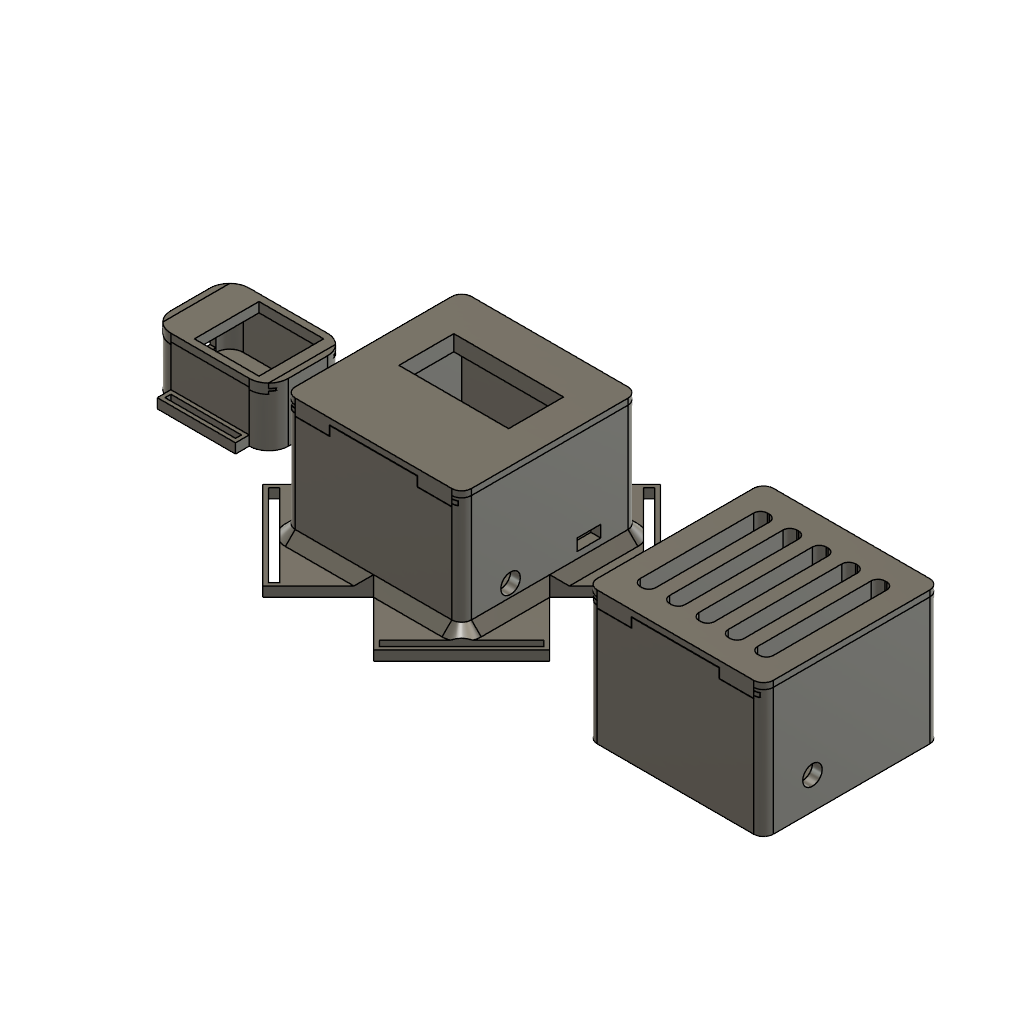
Vishwakarma (Autodesk Fusion 360 design; units mm, degrees)
Autodesk Fusion 360 part; units mm, degrees
sketch "Sketch1" plane through (0, 0, 0) normal (0, 1, 0) x (1, 0, 0) in component "Wrist unit"
  line L0 (20, 20) -> (-20, 20)
  line L1 (-30, 10) -> (-30, -10)
  line L2 (-20, -20) -> (20, -20)
  line L3 (30, -10) -> (30, 10)
  line L4 (30, 20) -> (-30, -20) construction
  line L5 (-30, 20) -> (30, -20) construction
  arc A0 (-20, 20) -> (-30, 10) centre (-20, 10) ccw
  arc A1 (30, 10) -> (20, 20) centre (20, 10) ccw
  arc A2 (20, -20) -> (30, -10) centre (20, -10) ccw
  arc A3 (-30, -10) -> (-20, -20) centre (-20, -10) ccw
  line L6 (-30, 0) -> (30, 0) construction
  line L7 (0, 0) -> (-30, 0) construction
  line L8 (0, 20) -> (0, -20) construction
  line L9 (5, -5) -> (-5, -5)
  line L10 (-5, -5) -> (-5, 5)
  line L11 (-5, 5) -> (5, 5)
  line L12 (5, 5) -> (5, -5)
  line L13 (5, -5) -> (-5, 5) construction
  line L14 (-5, -5) -> (5, 5) construction
  line L15 (-20, 20) -> (20, 20)
  line L16 (20, 20) -> (20, 27)
  line L17 (20, 27) -> (-20, 27)
  line L18 (-20, 27) -> (-20, 20)
  line L19 (-20, -20) -> (20, -20)
  line L20 (20, -20) -> (20, -27)
  line L21 (20, -27) -> (-20, -27)
  line L22 (-20, -27) -> (-20, -20)
  line L23 (-18, 22) -> (18, 22)
  line L24 (18, 22) -> (18, 25)
  line L25 (18, 25) -> (-18, 25)
  line L26 (-18, 25) -> (-18, 22)
  line L27 (-18, -22) -> (18, -22)
  line L28 (18, -22) -> (18, -25)
  line L29 (18, -25) -> (-18, -25)
  line L30 (-18, -25) -> (-18, -22)
  line L31 (30, 0) -> (5, 0) construction
  line L32 (-11.5, -16.5) -> (21.5, -16.5)
  line L33 (21.5, -16.5) -> (21.5, 16.5)
  line L34 (21.5, 16.5) -> (-11.5, 16.5)
  line L35 (-11.5, 16.5) -> (-11.5, -16.5)
  line L36 (-11.5, -16.5) -> (21.5, 16.5) construction
  line L37 (21.5, -16.5) -> (-11.5, 16.5) construction
  point P0 (5, 0)
  dimension "d219_1" = 60
  dimension "d220_1" = 40
  dimension "d221_1" = 10
  dimension "d222_1" = 10
  dimension "d113" = 10
  dimension "d114" = 10
  dimension "d115" = 40
  dimension "d116" = 7
  dimension "d117" = 40
  dimension "d118" = 7
  dimension "d119" = -2
  dimension "d120" = 2
  dimension "d124" = 25
  dimension "d125" = 33
  dimension "d126" = 33
  constraint horizontal L0
  constraint perpendicular L0 L1
  constraint parallel L0 L2
  constraint parallel L1 L3
  constraint coincident L4 L7.start
  constraint coincident L5 L7.start
  constraint coincident L7.start origin
  constraint coincident L5.start L1
  constraint coincident L5.start L0
  constraint tangent L1 A0
  constraint tangent L0 A0
  constraint coincident L4.start L3
  constraint coincident L4.start L0
  constraint tangent L3 A1
  constraint tangent L0 A1
  constraint coincident L5.end L3
  constraint coincident L5.end L2
  constraint tangent L3 A2
  constraint tangent L2 A2
  constraint equal A1 A2
  constraint coincident L4.end L1
  constraint coincident L4.end L2
  constraint tangent L1 A3
  constraint tangent L2 A3
  constraint equal A1 A3
  constraint midpoint L1 L6.start
  constraint midpoint L3 L6.end
  constraint midpoint L0 L8.start
  constraint midpoint L2 L8.end
  constraint horizontal L9
  constraint perpendicular L9 L10
  constraint parallel L9 L11
  constraint parallel L10 L12
  constraint coincident L13 L7.start
  constraint coincident L14 L7.start
  constraint horizontal L15
  constraint vertical L16
  constraint horizontal L17
  constraint vertical L18
  constraint horizontal L19
  constraint vertical L20
  constraint horizontal L21
  constraint vertical L22
  constraint parallel L6 L31
  constraint horizontal L32
  constraint perpendicular L32 L33
  constraint parallel L32 L34
  constraint parallel L33 L35
  constraint coincident L36 P0
  constraint coincident L37 P0
  constraint coincident P0 L31.end
  measures "d219_1" distance of L4.end L5.end
  measures "d220_1" distance of L5.start L4.end
  measures "d221_1" radius of A0
  measures "d222_1" radius of A1
  measures "d113" distance of L10.end L11.end
  measures "d114" distance of L9.end L10.end
  measures "d115" distance of L0.end L0.start
  measures "d116" distance of L0.end L17.end
  measures "d117" distance of L2.start L2.end
  measures "d118" distance of L2.start L21.end
  measures "d124" distance of L6.end P0
  measures "d125" distance of L33.end L34.end
  measures "d126" distance of L32.end L33.end
extrude "Extrude1" add sketch "Sketch1" against normal blind 25 contours L0 L1 L2 L3 A0 A1 A2 A3 L15 L19 | L9 L10 L11 L12 | L32 L33 L34 L35 makes body 1 in component "Wrist unit"
shell "Shell1" thickness 3 removed faces 1 at (-6.6667, 0, 6.6667) on bodies 1 in component "Wrist unit"
extrude "Extrude2" cut sketch "Sketch1" against normal blind 25 contours L9 L10 L11 L12 bodies 1 in component "Wrist unit"
extrude "Extrude3" add sketch "Sketch1" along normal blind 5 separate body contours L0 L1 L2 L3 A0 A1 A2 A3 L15 L19 makes body 2 in component "Wrist unit"
sketch "Sketch2" plane through (0, 0, 20) normal (0, 0, 1) x (1, 0, 0) in component "Wrist unit"
  line L0 (-20, 5) -> (-20, 0)
  line L1 (-20, -25) -> (20, -25)
  line L2 (20, 0) -> (20, 5)
  line L3 (20, 5) -> (-20, 5)
  line L4 (-20, 0) -> (20, 0)
  line L5 (20, 0) -> (-20, 0)
  line L6 (-20, 0) -> (-20, -25)
  line L7 (20, -25) -> (20, 0)
  line L8 (20, -1.25) -> (-20.041, -1.25)
  line L9 (-20.041, -1.25) -> (-20.041, 1.25)
  line L10 (-20.041, 1.25) -> (20, 1.25)
  line L11 (20, 1.25) -> (20, -1.25)
  line L12 (-19.941, -1.15) -> (-19.941, 1.15)
  line L13 (-19.941, 1.15) -> (19.9, 1.15)
  line L14 (19.9, 1.15) -> (19.9, -1.15)
  line L15 (19.9, -1.15) -> (-19.941, -1.15)
  line L16 (-20.041, 0) -> (-30, 0) construction
  line L17 (-30, 0) -> (-30, -5) construction
  line L18 (-30, -5) -> (-27, -5)
  line L19 (-27, -5) -> (-27, 5)
  line L20 (-27, 5) -> (-30, 5)
  line L21 (-30, 5) -> (-30, -5)
  line L22 (-27.1, 4.9) -> (-29.9, 4.9)
  line L23 (-29.9, 4.9) -> (-29.9, -4.9)
  line L24 (-29.9, -4.9) -> (-27.1, -4.9)
  line L25 (-27.1, -4.9) -> (-27.1, 4.9)
  line L26 (-19.941, -1.15) -> (-19.941, -1.25)
  line L27 (19.9, -1.15) -> (19.9, -1.25)
  line L28 (0, 0) -> (-0.0205, -1.15) construction
  line L29 (-29.9, -4.9) -> (-30, -4.8994)
  line L30 (-29.9, 4.9) -> (-30, 4.9)
  line L31 (0, 5) -> (0, -1) construction
  line L32 (-27.1, 4.9) -> (-27.1, 5) construction
  line L33 (-27.1, 0) -> (-27.1, 1.5) construction
  line L34 (-27.1, 1.5) -> (-28.6, 1.5)
  line L35 (-28.6, 1.5) -> (-28.6, 2.5)
  line L36 (-28.6, 2.5) -> (-27.1, 2.5)
  line L37 (-27.1, 2.5) -> (-27.1, 1.5)
  line L38 (-27.1, 1.4) -> (-28.7, 1.4)
  line L39 (-28.7, 1.4) -> (-28.7, 2.6)
  line L40 (-28.7, 2.6) -> (-27.1, 2.6)
  line L41 (-27.1, 1.4) -> (-27.1, 0)
  line L42 (28.7, 1.4) -> (28.7, 2.6)
  line L43 (27.1, 1.4) -> (27.1, 0)
  line L44 (27.1, -4.9) -> (27.1, 4.9)
  line L45 (27.1, 2.5) -> (27.1, 1.5)
  line L46 (27, -5) -> (27, 5)
  line L47 (29.9, -4.9) -> (27.1, -4.9)
  line L48 (27.1, 1.5) -> (28.6, 1.5)
  line L49 (28.7, 2.6) -> (27.1, 2.6)
  line L50 (27.1, 0) -> (27.1, 1.5) construction
  line L51 (30, 5) -> (30, -5)
  line L52 (27.1, 4.9) -> (29.9, 4.9)
  line L53 (29.9, -4.9) -> (30, -4.8994)
  line L54 (27.1, 4.9) -> (27.1, 5) construction
  line L55 (27.1, 1.4) -> (28.7, 1.4)
  line L56 (27, 5) -> (30, 5)
  line L57 (28.6, 1.5) -> (28.6, 2.5)
  line L58 (30, 0) -> (30, -5) construction
  line L59 (29.9, 4.9) -> (30, 4.9)
  line L60 (30, -5) -> (27, -5)
  line L61 (28.6, 2.5) -> (27.1, 2.5)
  line L62 (29.9, 4.9) -> (29.9, -4.9)
  line L63 (27.1, 2.6) -> (27, 2.6)
  line L64 (27.1, 2.5) -> (27, 2.5)
  line L65 (27.1, 1.5) -> (27, 1.5)
  line L66 (27.1, 1.4) -> (27, 1.4)
  line L67 (-27.1, 2.6) -> (-27, 2.6)
  line L68 (-27.1, 2.5) -> (-27, 2.5)
  line L69 (-27.1, 1.5) -> (-27, 1.5)
  line L70 (-27.1, 1.4) -> (-27, 1.4)
  point P0 (-30, 0)
  point P1 (30, 0)
  dimension "d238_1" = 2.5
  dimension "d239_1" = 0.1
  dimension "d241_1" = 3
  dimension "d242_1" = 10
  dimension "d243_1" = -0.1
  dimension "d254_1" = 6
  dimension "d255_1" = 1.5
  dimension "d256_1" = 1
  dimension "d257_1" = -0.1
  constraint horizontal L8
  constraint vertical L9
  constraint horizontal L10
  constraint vertical L11
  constraint coincident L7 L8.start
  constraint midpoint L9 L16.start
  constraint perpendicular L9 L16
  constraint perpendicular L8 L17
  constraint horizontal L18
  constraint vertical L19
  constraint horizontal L20
  constraint vertical L21
  constraint coincident L8 L26.end
  constraint perpendicular L8 L26
  constraint coincident L8 L27.end
  constraint perpendicular L8 L27
  constraint coincident L28.start origin
  constraint midpoint L15 L28.end
  constraint coincident L17 L29.end
  constraint coincident L21 L30.end
  constraint perpendicular L21 L30
  constraint midpoint L3 L31.start
  constraint perpendicular L15 L31
  constraint coincident L20 L32.end
  constraint perpendicular L20 L32
  constraint midpoint L21 P0
  constraint midpoint L25 L33.start
  constraint coincident L25 L33.end
  constraint horizontal L34
  constraint vertical L35
  constraint horizontal L36
  constraint vertical L37
  constraint perpendicular L16 L41
  constraint symmetric P0 L31 P1
  constraint symmetric L17.end L31 L51.end
  constraint symmetric L18.end L31 L46.start
  constraint symmetric L19.end L31 L46.end
  constraint symmetric L20.end L31 L51.start
  constraint symmetric L22.start L31 L44.end
  constraint symmetric L22.end L31 L52.end
  constraint symmetric L23.end L31 L47.start
  constraint symmetric L24.end L31 L44.start
  constraint symmetric L29.end L31 L53.end
  constraint symmetric L30.end L31 L59.end
  constraint symmetric L31 L32.end L54.end
  constraint symmetric L31 P0 P1
  constraint symmetric L31 L33.start L43.end
  constraint symmetric L31 L33.end L45.end
  constraint symmetric L31 L34.end L48.end
  constraint symmetric L31 L35.end L57.end
  constraint symmetric L31 L36.end L45.start
  constraint symmetric L31 L38.start L43.start
  constraint symmetric L31 L38.end L42.start
  constraint symmetric L31 L39.end L42.end
  constraint symmetric L31 L40.end L49.end
  constraint coincident L46 L63.end
  constraint perpendicular L46 L63
  constraint coincident L46 L64.end
  constraint perpendicular L46 L64
  constraint coincident L46 L65.end
  constraint perpendicular L46 L65
  constraint coincident L46 L66.end
  constraint perpendicular L46 L66
  constraint coincident L19 L67.end
  constraint perpendicular L19 L67
  constraint coincident L19 L68.end
  constraint perpendicular L19 L68
  constraint coincident L19 L69.end
  constraint perpendicular L19 L69
  constraint coincident L19 L70.end
  constraint perpendicular L19 L70
  measures "d238_1" distance of L8.start L10.end
  measures "d241_1" distance of L17.end L18.end
  measures "d242_1" distance of L17.end L20.end
  measures "d254_1" distance of L31.start L31.end
  measures "d255_1" distance of L33.end L34.end
  measures "d256_1" distance of L33.end L36.end
extrude "Extrude4" add sketch "Sketch2" against normal blind 2 contours L4 L5 L12 L13 L14 | L4 L5 L12 L14 L15 | L8 L15 L26 L27 bodies 1 in component "Wrist unit"
extrude "Extrude5" cut sketch "Sketch2" against normal blind 2 contours L4 L5 L12 L13 L14 | L4 L5 L12 L14 L15 bodies 2 in component "Wrist unit"
extrude "Extrude6" add sketch "Sketch2" against normal blind 51 contours L18 L19 L21 L24 L25 L29 L41 L70 | L21 L23 L29 L30 | L19 L20 L21 L22 L25 L30 L67 | L22 L23 L24 L25 L38 L39 L40 L41 | L42 L43 L44 L47 L49 L52 L55 L62 | L43 L44 L46 L47 L51 L53 L60 L66 | L44 L46 L51 L52 L56 L59 L63 | L51 L53 L59 L62 bodies 1 in component "Wrist unit"
extrude "Extrude9" cut sketch "Sketch2" against normal blind 45 contours L18 L19 L21 L24 L25 L29 L41 L70 | L21 L23 L29 L30 | L19 L25 L69 L70 | L19 L20 L21 L22 L25 L30 L67 | L22 L23 L24 L25 L38 L39 L40 L41 | L25 L34 L35 L36 L38 L39 L40 | L19 L25 L67 L68 | L42 L44 L48 L49 L55 L57 L61 | L42 L43 L44 L47 L49 L52 L55 L62 | L44 L46 L65 L66 | L43 L44 L46 L47 L51 L53 L60 L66 | L44 L46 L51 L52 L56 L59 L63 | L44 L46 L63 L64 | L51 L53 L59 L62 bodies 2 in component "Wrist unit"
extrude "Extrude10" cut sketch "Sketch1" along normal mid plane 70 contours L0 L1 L2 L3 A0 A1 A2 A3 L15 L19 | L9 L10 L11 L12 | L32 L33 L34 L35 keep common part bodies 1 in component "Wrist unit"
extrude "Extrude11" add sketch "Sketch1" against normal blind 5 from surface at -20 contours L0 L15 L16 L17 L18 | L2 L19 L20 L21 L22 bodies 1 in component "Wrist unit"
sketch "Sketch1 (2)" plane through (0, 0, 0) normal (0, 1, 0) x (1, 0, 0) in component "Gas Unit"
  arc A0 (68.5599, -45.076) -> (73.5599, -50.076) centre (73.5599, -45.076) ccw
  line L0 (68.5599, -45.076) -> (68.5599, 34.924)
  line L1 (73.5599, 34.924) -> (153.5599, 34.924)
  line L2 (73.5599, -45.076) -> (153.5599, 34.924) construction
  line L3 (73.5599, -45.076) -> (73.5599, 34.924)
  line L4 (73.5599, 39.924) -> (153.5599, 39.924)
  line L5 (153.5599, -45.076) -> (73.5599, 34.924) construction
  line L6 (153.5599, -50.076) -> (73.5599, -50.076)
  arc A1 (73.5599, 39.924) -> (68.5599, 34.924) centre (73.5599, 34.924) ccw
  line L7 (153.5599, -45.076) -> (73.5599, -45.076)
  line L8 (158.5599, 34.924) -> (158.5599, -45.076)
  arc A2 (158.5599, 34.924) -> (153.5599, 39.924) centre (153.5599, 34.924) ccw
  arc A3 (153.5599, -50.076) -> (158.5599, -45.076) centre (153.5599, -45.076) ccw
  line L9 (153.5599, 34.924) -> (153.5599, -45.076)
  line L10 (114.0599, 27.424) -> (113.0599, 27.424)
  line L11 (109.5599, 23.924) -> (109.5599, -34.076)
  line L12 (113.0599, -37.576) -> (114.0599, -37.576)
  line L13 (117.5599, -34.076) -> (117.5599, 23.924)
  line L14 (117.5599, 27.424) -> (109.5599, -37.576) construction
  line L15 (109.5599, 27.424) -> (117.5599, -37.576) construction
  arc A4 (109.5599, -34.076) -> (113.0599, -37.576) centre (113.0599, -34.076) ccw
  arc A5 (114.0599, -37.576) -> (117.5599, -34.076) centre (114.0599, -34.076) ccw
  arc A6 (117.5599, 23.924) -> (114.0599, 27.424) centre (114.0599, 23.924) ccw
  arc A7 (113.0599, 27.424) -> (109.5599, 23.924) centre (113.0599, 23.924) ccw
  line L16 (84.0599, 27.424) -> (83.0599, 27.424)
  arc A8 (83.0599, 27.424) -> (79.5599, 23.924) centre (83.0599, 23.924) ccw
  line L17 (79.5599, 23.924) -> (79.5599, -34.076)
  arc A9 (79.5599, -34.076) -> (83.0599, -37.576) centre (83.0599, -34.076) ccw
  line L18 (83.0599, -37.576) -> (84.0599, -37.576)
  arc A10 (84.0599, -37.576) -> (87.5599, -34.076) centre (84.0599, -34.076) ccw
  arc A11 (87.5599, 23.924) -> (84.0599, 27.424) centre (84.0599, 23.924) ccw
  line L19 (87.5599, -34.076) -> (87.5599, 23.924)
  line L20 (99.0599, 27.424) -> (98.0599, 27.424)
  arc A12 (98.0599, 27.424) -> (94.5599, 23.924) centre (98.0599, 23.924) ccw
  line L21 (94.5599, 23.924) -> (94.5599, -34.076)
  arc A13 (94.5599, -34.076) -> (98.0599, -37.576) centre (98.0599, -34.076) ccw
  line L22 (98.0599, -37.576) -> (99.0599, -37.576)
  arc A14 (99.0599, -37.576) -> (102.5599, -34.076) centre (99.0599, -34.076) ccw
  arc A15 (102.5599, 23.924) -> (99.0599, 27.424) centre (99.0599, 23.924) ccw
  line L23 (102.5599, -34.076) -> (102.5599, 23.924)
  line L24 (129.0599, 27.424) -> (128.0599, 27.424)
  arc A16 (128.0599, 27.424) -> (124.5599, 23.924) centre (128.0599, 23.924) ccw
  line L25 (124.5599, 23.924) -> (124.5599, -34.076)
  arc A17 (124.5599, -34.076) -> (128.0599, -37.576) centre (128.0599, -34.076) ccw
  line L26 (128.0599, -37.576) -> (129.0599, -37.576)
  arc A18 (129.0599, -37.576) -> (132.5599, -34.076) centre (129.0599, -34.076) ccw
  arc A19 (132.5599, 23.924) -> (129.0599, 27.424) centre (129.0599, 23.924) ccw
  line L27 (132.5599, -34.076) -> (132.5599, 23.924)
  line L28 (144.0599, 27.424) -> (143.0599, 27.424)
  arc A20 (143.0599, 27.424) -> (139.5599, 23.924) centre (143.0599, 23.924) ccw
  line L29 (139.5599, 23.924) -> (139.5599, -34.076)
  arc A21 (139.5599, -34.076) -> (143.0599, -37.576) centre (143.0599, -34.076) ccw
  line L30 (143.0599, -37.576) -> (144.0599, -37.576)
  arc A22 (144.0599, -37.576) -> (147.5599, -34.076) centre (144.0599, -34.076) ccw
  arc A23 (147.5599, 23.924) -> (144.0599, 27.424) centre (144.0599, 23.924) ccw
  line L31 (147.5599, -34.076) -> (147.5599, 23.924)
  point P0 (113.5599, -5.076)
  point P1 (113.5599, -5.076)
  dimension "d7" = 80
  dimension "d8" = 80
  dimension "d9" = 5
  dimension "d10" = 5
  dimension "d11" = 5
  dimension "d12" = 5
  dimension "d13" = 5
  dimension "d14" = 5
  dimension "d102" = 8
  dimension "d103" = 65
  dimension "d104" = 3.5
  dimension "d107" = 30
  dimension "d108" = 0
  constraint horizontal L7
  constraint perpendicular L3 L7
  constraint parallel L1 L7
  constraint parallel L3 L9
  constraint tangent L4 A1
  constraint tangent L0 A1
  constraint tangent L4 A2
  constraint tangent L8 A2
  constraint tangent L8 A3
  constraint tangent L6 A3
  constraint equal A2 A3
  constraint tangent A0 L0
  constraint tangent A0 L6
  constraint equal A0 A2
  constraint horizontal L10
  constraint perpendicular L10 L11
  constraint parallel L10 L12
  constraint parallel L11 L13
  constraint coincident L14 P1
  constraint coincident L15 P1
  constraint coincident P1 P0
  constraint coincident L14.end L11
  constraint coincident L14.end L12
  constraint tangent L11 A4
  constraint tangent L12 A4
  constraint coincident L15.end L12
  constraint coincident L15.end L13
  constraint tangent L12 A5
  constraint tangent L13 A5
  constraint equal A4 A5
  constraint coincident L14.start L10
  constraint coincident L14.start L13
  constraint tangent L10 A6
  constraint tangent L13 A6
  constraint equal A4 A6
  constraint coincident L15.start L11
  constraint coincident L15.start L10
  constraint tangent L11 A7
  constraint tangent L10 A7
  constraint equal A4 A7
  measures "d7" distance of L1.start L1.end
  measures "d8" distance of L1.start A0.centre
  measures "d9" distance of L6 L7
  measures "d10" distance of L0 L3
  measures "d11" distance of L1 L4
  measures "d12" distance of L8 L9
  measures "d13" radius of A1
  measures "d14" radius of A2
  measures "d102" distance of L14.end L15.end
  measures "d103" distance of L15.start L14.end
  measures "d104" radius of A4
  measures "d222_1" radius of L1.end
extrude "Extrude1'" add sketch "Sketch1 (2)" along normal blind 60 separate body contours A0 L0 L4 L6 A1 L8 A2 A3 | L1 L3 L7 L9 | L10 L11 L12 L13 A4 A5 A6 A7 | L16 A8 L17 A9 L18 A10 A11 L19 | L20 A12 L21 A13 L22 A14 A15 L23 | L24 A16 L25 A17 L26 A18 A19 L27 | L28 A20 L29 A21 L30 A22 A23 L31 makes body 3 in component "Gas Unit"
extrude "Extrude2'" cut sketch "Sketch1 (2)" along normal blind 57 contours L1 L3 L7 L9 | L10 L11 L12 L13 A4 A5 A6 A7 | L16 A8 L17 A9 L18 A10 A11 L19 | L20 A12 L21 A13 L22 A14 A15 L23 | L24 A16 L25 A17 L26 A18 A19 L27 | L28 A20 L29 A21 L30 A22 A23 L31 bodies 3 in component "Gas Unit"
extrude "Extrude3'" add sketch "Sketch1 (2)" against normal blind 8 from surface at -0.1 separate body contours A0 L0 L4 L6 A1 L8 A2 A3 | L1 L3 L7 L9 makes body 4 in component "Gas Unit"
sketch "Sketch2 (2)" plane through (0, 0, -39.924) normal (0, 0, -1) x (-1, 0, 0) in component "Gas Unit"
  line L0 (-153.5599, 0) -> (-73.5599, 0)
  line L1 (-73.5599, 0) -> (-73.5599, 60)
  line L2 (-73.5599, 60) -> (-153.5599, 60)
  line L3 (-153.5599, 60) -> (-153.5599, 0)
  line L4 (-113.5599, 0) -> (-113.5599, -8) construction
  line L5 (-136.0599, -5) -> (-91.0599, -5)
  line L6 (-91.0599, -5) -> (-91.0599, 5)
  line L7 (-91.0599, 5) -> (-136.0599, 5)
  line L8 (-136.0599, 5) -> (-136.0599, -5)
  line L9 (-136.0599, -5) -> (-91.0599, 5) construction
  line L10 (-91.0599, -5) -> (-136.0599, 5) construction
  line L11 (-91.2599, 4.8) -> (-135.8599, 4.8)
  line L12 (-135.8599, 4.8) -> (-135.8599, -4.8)
  line L13 (-135.8599, -4.8) -> (-91.2599, -4.8)
  line L14 (-91.2599, -4.8) -> (-91.2599, 4.8)
  line L15 (-73.5599, 1.4) -> (-70.9599, 1.4) construction
  line L16 (-68.6599, 4.9) -> (-73.4599, 4.9)
  line L17 (-71.0599, 3.5) -> (-73.5599, 3.5) construction
  line L18 (-70.9599, 3.6) -> (-73.5599, 3.6) construction
  line L19 (-73.4599, -4.9) -> (-68.6599, -4.9)
  line L20 (-68.5599, 5) -> (-73.5599, 5)
  line L21 (-73.5599, 0) -> (-68.5599, 0) construction
  line L22 (-73.5599, 0) -> (-73.5599, 1.5) construction
  line L23 (-70.9599, 1.4) -> (-70.9599, 3.6) construction
  line L24 (-73.5599, -3.5) -> (-73.5599, -1.5)
  line L25 (-73.5599, -1.4) -> (-70.9599, -1.4)
  line L26 (-73.4599, 4.9) -> (-73.4599, -4.9)
  line L27 (-68.5599, -5) -> (-68.5599, 5)
  line L28 (-73.5599, 1.5) -> (-71.0599, 1.5) construction
  line L29 (-73.5599, -5) -> (-68.5599, -5)
  line L30 (-73.5599, -5) -> (-68.5599, 5) construction
  line L31 (-73.5599, -1.5) -> (-71.0599, -1.5)
  line L32 (-71.0599, -3.5) -> (-73.5599, -3.5)
  line L33 (-71.0599, 1.5) -> (-71.0599, 3.5) construction
  line L34 (-68.5599, -5) -> (-73.5599, 5) construction
  line L35 (-71.0599, -1.5) -> (-71.0599, -3.5)
  line L36 (-73.5599, 3.5) -> (-73.5599, 1.5) construction
  line L37 (-70.9599, -3.6) -> (-73.5599, -3.6)
  line L38 (-68.6599, -4.9) -> (-68.6599, 4.9)
  line L39 (-73.5599, 5) -> (-73.5599, -5)
  line L40 (-70.9599, -1.4) -> (-70.9599, -3.6)
  line L41 (-73.5599, 0) -> (-71.0599, 0) construction
  line L42 (-153.5599, 0) -> (-156.0599, 0) construction
  line L43 (-153.5599, 0) -> (-158.5599, 0) construction
  line L44 (-153.5599, -1.5) -> (-156.0599, -1.5)
  line L45 (-153.5599, -5) -> (-158.5599, 5) construction
  line L46 (-153.5599, 0) -> (-153.5599, 1.5) construction
  line L47 (-153.5599, -5) -> (-158.5599, -5)
  line L48 (-153.5599, -1.4) -> (-156.1599, -1.4)
  line L49 (-156.0599, -1.5) -> (-156.0599, -3.5)
  line L50 (-153.5599, 5) -> (-153.5599, -5)
  line L51 (-153.6599, -4.9) -> (-158.4599, -4.9)
  line L52 (-156.1599, -3.6) -> (-153.5599, -3.6)
  line L53 (-153.5599, -3.5) -> (-153.5599, -1.5)
  line L54 (-153.6599, 4.9) -> (-153.6599, -4.9)
  line L55 (-158.4599, -4.9) -> (-158.4599, 4.9)
  line L56 (-156.1599, -1.4) -> (-156.1599, -3.6)
  line L57 (-158.5599, -5) -> (-158.5599, 5)
  line L58 (-153.5599, 1.4) -> (-156.1599, 1.4) construction
  line L59 (-156.1599, 3.6) -> (-153.5599, 3.6) construction
  line L60 (-156.0599, -3.5) -> (-153.5599, -3.5)
  line L61 (-158.5599, -5) -> (-153.5599, 5) construction
  line L62 (-158.4599, 4.9) -> (-153.6599, 4.9)
  line L63 (-153.5599, 3.5) -> (-153.5599, 1.5) construction
  line L64 (-156.0599, 3.5) -> (-153.5599, 3.5) construction
  line L65 (-156.0599, 1.5) -> (-156.0599, 3.5) construction
  line L66 (-156.1599, 1.4) -> (-156.1599, 3.6) construction
  line L67 (-153.5599, 1.5) -> (-156.0599, 1.5) construction
  line L68 (-158.5599, 5) -> (-153.5599, 5)
  point P0 (-113.5599, 0)
  point P1 (-71.0599, 0)
  point P2 (-156.0599, 0)
  point P3 (-153.5599, 0)
  dimension "d74" = 45
  dimension "d75" = 10
  dimension "d77" = -0.2
  dimension "d88" = -0.1
  dimension "d89" = 5
  dimension "d90" = 1.5
  dimension "d91" = 2.5
  dimension "d92" = 2
  dimension "d93" = 0.1
  dimension "d94" = 0.1
  dimension "d95" = 0.1
  dimension "d96" = 2.5
  constraint midpoint L0 P0
  constraint perpendicular L0 L4
  constraint horizontal L5
  constraint perpendicular L5 L6
  constraint parallel L5 L7
  constraint parallel L6 L8
  constraint coincident L9 P0
  constraint coincident L10 P0
  constraint coincident P0 L4.start
  constraint perpendicular L27 L29
  constraint parallel L20 L29
  constraint parallel L27 L39
  constraint coincident P1 L30
  constraint coincident P1 L34
  constraint midpoint P1 L21
  constraint perpendicular L21 L22
  constraint symmetric L22.end L24.end L21
  constraint symmetric L31.end L28.end L21
  constraint symmetric L17.start L32.start L21
  constraint symmetric L24.start L17.end L21
  constraint symmetric L25.end L15.end L21
  constraint symmetric L37.start L18.start L21
  constraint symmetric L25.start L15.start L21
  constraint symmetric L37.end L18.end L21
  constraint coincident L0.end L1.start
  constraint perpendicular L1 L41
  constraint symmetric L0.end L4 P3
  constraint symmetric L4 L17.start L64.start
  constraint symmetric L4 P1 P2
  constraint symmetric L4 L22.end L46.end
  constraint symmetric L4 L32.start L49.end
  constraint symmetric L4 L25.end L48.end
  constraint symmetric L4 L37.end L52.end
  constraint symmetric L4 L25.start L48.start
  constraint symmetric L4 L24.start L53.start
  constraint symmetric L4 L31.end L44.end
  constraint symmetric L4 L24.end L44.start
  constraint symmetric L4 L37.start L52.start
  constraint symmetric L4 L28.end L65.start
  constraint symmetric L4 L20.start L45.end
  constraint symmetric L4 L0.end P3
  constraint symmetric L4 L29.start L45.start
  constraint symmetric L4 L21.end L43.end
  constraint symmetric L4 L27.start L47.end
  constraint symmetric L4 L20.end L50.start
  constraint symmetric L4 L15.end L58.end
  constraint symmetric L4 L18.start L59.start
  constraint symmetric L4 L17.end L63.start
  constraint symmetric L4 L15.start L58.start
  constraint symmetric L4 L18.end L59.end
  constraint symmetric L4 L16.start L55.end
  constraint symmetric L4 L19.end L51.end
  constraint symmetric L4 L19.start L51.start
  constraint symmetric L4 L16.end L54.start
  measures "d74" distance of L6.end L7.end
  measures "d75" distance of L5.end L6.end
  measures "d89" distance of L0.end L21.end
  measures "d90" distance of L22.end L0.end
  measures "d91" distance of L22.end L28.end
  measures "d92" distance of L22.end L17.end
  measures "d93" distance of L15 L28
  measures "d94" distance of L23 L33
  measures "d95" distance of L17 L18
  measures "d96" distance of L0.end P1
extrude "Extrude4'" add sketch "Sketch2 (2)" against normal blind 2.5 contours L0 L12 L13 L14 bodies 3 in component "Gas Unit"
extrude "Extrude5'" cut sketch "Sketch2 (2)" against normal blind 2.5 contours L0 L5 L6 L8 L12 L13 L14 | L0 L12 L13 L14 bodies 4 in component "Gas Unit"
extrude "Extrude6'" add sketch "Sketch2 (2)" against normal blind 90 contours L3 L47 L48 L50 L51 L52 L54 L55 L57 L62 L68 | L48 L51 L52 L54 L55 L56 L62 | L1 L16 L19 L20 L25 L26 L27 L29 L37 L38 L39 | L16 L19 L25 L26 L37 L38 L40 bodies 3 in component "Gas Unit"
extrude "Extrude7" cut sketch "Sketch2 (2)" against normal blind 90 contours L3 L47 L48 L50 L51 L52 L54 L55 L57 L62 L68 | L44 L48 L50 L54 | L44 L48 L49 L52 L54 L56 L60 | L48 L51 L52 L54 L55 L56 L62 | L50 L52 L54 L60 | L1 L16 L19 L20 L25 L26 L27 L29 L37 L38 L39 | L25 L26 L31 L39 | L16 L19 L25 L26 L37 L38 L40 | L25 L26 L31 L32 L35 L37 L40 | L26 L32 L37 L39 bodies 4 in component "Gas Unit"
extrude "Extrude8" cut sketch "Sketch1 (2)" along normal mid plane 130 contours A0 L0 L4 L6 A1 L8 A2 A3 | L1 L3 L7 L9 | L10 L11 L12 L13 A4 A5 A6 A7 | L16 A8 L17 A9 L18 A10 A11 L19 | L20 A12 L21 A13 L22 A14 A15 L23 | L24 A16 L25 A17 L26 A18 A19 L27 | L28 A20 L29 A21 L30 A22 A23 L31 keep common part bodies 3 in component "Gas Unit"
sketch "Sketch3" plane through (158.5599, 0, 0) normal (1, 0, 0) x (0, 0, -1) in component "Gas Unit"
  line L0 (34.924, -5) -> (34.924, 60)
  line L1 (34.924, 60) -> (-45.076, 60)
  line L2 (-45.076, 60) -> (-45.076, -5)
  line L3 (-45.076, -5) -> (34.924, -5)
  line L4 (34.924, 27.5) -> (-45.076, 27.5) construction
  line L5 (34.924, 60) -> (-5.076, 27.5) construction
  circle A0 centre (14.924, 43.75) radius 5
  dimension "d110" = 10
  constraint midpoint L0 L4.start
  constraint midpoint L2 L4.end
  constraint coincident L0.end L1.start
  constraint midpoint L4 L5.end
  constraint midpoint L5 A0.centre
  measures "d110" diameter of A0
extrude "Extrude9'" cut sketch "Sketch3" against normal blind 5 contours A0 bodies 3 in component "Gas Unit"
sketch "Sketch4" plane through (0, 0, 50.076) normal (0, 0, 1) x (1, 0, 0) in component "Gas Unit"
  line L0 (153.5599, 0) -> (153.5599, 60)
  line L1 (153.5599, 60) -> (73.5599, 60)
  line L2 (73.5599, 60) -> (73.5599, 0)
  line L3 (73.5599, 0) -> (153.5599, 0)
  line L4 (153.5599, 0) -> (73.5599, 60) construction
  line L5 (141.5599, 44) -> (85.5599, 44)
  line L6 (85.5599, 44) -> (85.5599, 16)
  line L7 (85.5599, 16) -> (141.5599, 16)
  line L8 (141.5599, 16) -> (141.5599, 44)
  line L9 (141.5599, 44) -> (85.5599, 16) construction
  line L10 (85.5599, 44) -> (141.5599, 16) construction
  point P0 (113.5599, 30)
  dimension "d131" = 56
  dimension "d132" = 28
  constraint coincident L0.start L3.end
  constraint coincident L1.end L2.start
  constraint horizontal L5
  constraint perpendicular L5 L6
  constraint parallel L5 L7
  constraint parallel L6 L8
  constraint coincident L9 P0
  constraint coincident L10 P0
  constraint midpoint L4 P0
  measures "d131" distance of L6.end L7.end
  measures "d132" distance of L5.end L6.end
extrude "Extrude11'" cut sketch "Sketch4" against normal blind 5 contours L5 L6 L7 L8 bodies 3 in component "Gas Unit"
sketch "Sketch1 (3)" plane through (0, 0, 0) normal (0, 1, 0) x (1, 0, 0) in component "Cheast Unit"
  arc A0 (68.5599, -45.076) -> (73.5599, -50.076) centre (73.5599, -45.076) ccw
  line L0 (68.5599, -45.076) -> (68.5599, 34.924)
  line L1 (73.5599, 34.924) -> (153.5599, 34.924)
  line L2 (73.5599, -45.076) -> (153.5599, 34.924) construction
  line L3 (73.5599, -45.076) -> (73.5599, 34.924)
  line L4 (73.5599, 39.924) -> (153.5599, 39.924)
  line L5 (153.5599, -45.076) -> (73.5599, 34.924) construction
  line L6 (153.5599, -50.076) -> (73.5599, -50.076)
  arc A1 (73.5599, 39.924) -> (68.5599, 34.924) centre (73.5599, 34.924) ccw
  line L7 (153.5599, -45.076) -> (73.5599, -45.076)
  line L8 (158.5599, 34.924) -> (158.5599, -45.076)
  arc A2 (158.5599, 34.924) -> (153.5599, 39.924) centre (153.5599, 34.924) ccw
  arc A3 (153.5599, -50.076) -> (158.5599, -45.076) centre (153.5599, -45.076) ccw
  line L9 (153.5599, 34.924) -> (153.5599, -45.076)
  line L10 (113.5599, -45.076) -> (113.5599, -15.076) construction
  line L11 (141.5599, -29.076) -> (85.5599, -29.076)
  line L12 (85.5599, -29.076) -> (85.5599, -1.076)
  line L13 (85.5599, -1.076) -> (141.5599, -1.076)
  line L14 (141.5599, -1.076) -> (141.5599, -29.076)
  line L15 (141.5599, -29.076) -> (85.5599, -1.076) construction
  line L16 (85.5599, -29.076) -> (141.5599, -1.076) construction
  line L17 (68.5599, -5.076) -> (68.5599, -50.076) construction
  line L18 (68.5599, -50.076) -> (113.5599, -50.076) construction
  line L19 (68.5599, -5.076) -> (113.5599, -50.076)
  line L20 (113.5599, -50.076) -> (85.2756, -78.3603)
  line L21 (85.2756, -78.3603) -> (40.2756, -33.3603)
  line L22 (40.2756, -33.3603) -> (68.5599, -5.076)
  line L23 (40.2756, -33.3603) -> (43.2756, -33.3603) construction
  line L24 (85.2756, -78.3603) -> (85.2756, -75.3603) construction
  line L25 (43.2756, -33.3603) -> (85.2756, -75.3603)
  line L26 (85.2756, -75.3603) -> (88.1041, -72.5319)
  line L27 (88.1041, -72.5319) -> (46.1041, -30.5319)
  line L28 (46.1041, -30.5319) -> (43.2756, -33.3603)
  line L29 (141.8442, -78.3603) -> (113.5599, -50.076)
  line L30 (113.5599, -50.076) -> (158.5599, -5.076)
  line L31 (186.8442, -33.3603) -> (141.8442, -78.3603)
  line L32 (158.5599, -5.076) -> (186.8442, -33.3603)
  line L33 (141.8442, -75.3603) -> (183.8442, -33.3603)
  line L34 (183.8442, -33.3603) -> (181.0157, -30.5319)
  line L35 (139.0157, -72.5319) -> (141.8442, -75.3603)
  line L36 (181.0157, -30.5319) -> (139.0157, -72.5319)
  line L37 (186.8442, 23.2082) -> (158.5599, -5.076)
  line L38 (158.5599, -5.076) -> (113.5599, 39.924)
  line L39 (141.8442, 68.2082) -> (186.8442, 23.2082)
  line L40 (113.5599, 39.924) -> (141.8442, 68.2082)
  line L41 (183.8442, 23.2082) -> (141.8442, 65.2082)
  line L42 (141.8442, 65.2082) -> (139.0157, 62.3798)
  line L43 (181.0157, 20.3798) -> (183.8442, 23.2082)
  line L44 (139.0157, 62.3798) -> (181.0157, 20.3798)
  line L45 (85.2756, 68.2082) -> (113.5599, 39.924)
  line L46 (113.5599, 39.924) -> (68.5599, -5.076)
  line L47 (40.2756, 23.2082) -> (85.2756, 68.2082)
  line L48 (68.5599, -5.076) -> (40.2756, 23.2082)
  line L49 (85.2756, 65.2082) -> (43.2756, 23.2082)
  line L50 (43.2756, 23.2082) -> (46.1041, 20.3798)
  line L51 (88.1041, 62.3798) -> (85.2756, 65.2082)
  line L52 (46.1041, 20.3798) -> (88.1041, 62.3798)
  point P0 (113.5599, -5.076)
  point P1 (113.5599, -5.076)
  point P2 (113.5599, -15.076)
  dimension "d7_1" = 80
  dimension "d8_1" = 80
  dimension "d9_1" = 5
  dimension "d10_1" = 5
  dimension "d11_1" = 5
  dimension "d12_1" = 5
  dimension "d13_1" = 5
  dimension "d14_1" = 5
  dimension "d135" = 30
  dimension "d136" = 56
  dimension "d137" = 28
  dimension "d140" = 40
  dimension "d141" = 3
  dimension "d142" = 3
  dimension "d143" = 4
  dimension "d145" = 360
  constraint horizontal L7
  constraint perpendicular L3 L7
  constraint parallel L1 L7
  constraint parallel L3 L9
  constraint tangent L4 A1
  constraint tangent L0 A1
  constraint tangent L4 A2
  constraint tangent L8 A2
  constraint tangent L8 A3
  constraint tangent L6 A3
  constraint equal A2 A3
  constraint tangent A0 L0
  constraint tangent A0 L6
  constraint equal A0 A2
  constraint coincident P1 P0
  constraint midpoint L7 L10.start
  constraint perpendicular L7 L10
  constraint horizontal L11
  constraint perpendicular L11 L12
  constraint parallel L11 L13
  constraint parallel L12 L14
  constraint coincident L15 P2
  constraint coincident L16 P2
  constraint coincident P2 L10.end
  constraint midpoint L0 L17.start
  constraint parallel L0 L17
  constraint midpoint L6 L18.end
  constraint perpendicular L17 L18
  constraint perpendicular L19 L20
  constraint parallel L19 L21
  constraint parallel L20 L22
  constraint horizontal L23
  constraint vertical L24
  constraint perpendicular L25 L26
  constraint parallel L25 L27
  constraint parallel L26 L28
  measures "d7_1" distance of L1.start L1.end
  measures "d8_1" distance of L1.start A0.centre
  measures "d9_1" distance of L6 L7
  measures "d10_1" distance of L0 L3
  measures "d11_1" distance of L1 L4
  measures "d12_1" distance of L8 L9
  measures "d13_1" radius of A1
  measures "d14_1" radius of A2
  measures "d135" distance of L10.start P2
  measures "d136" distance of L12.end L13.end
  measures "d137" distance of L11.end L12.end
  measures "d140" distance of L17.start L21.end
  measures "d141" distance of L21.end L23.end
  measures "d142" distance of L20.end L24.end
  measures "d143" distance of L23.end L27.end
extrude "Extrude1''" add sketch "Sketch1 (3)" along normal blind 60 separate body contours A0 L0 L3 L6 L7 L19 | L3 L19 L46 | L0 L1 L3 L4 A1 L46 | L6 L7 L8 A3 L9 L30 | L7 L19 L30 | L3 L7 L11 L12 L19 | L1 L3 L9 L12 L13 L14 L19 L30 L38 L46 | L1 L3 L46 | L7 L11 L19 L30 | L7 L9 L11 L14 L30 | L11 L12 L19 | L11 L12 L13 L14 L19 L30 | L1 L38 L46 | L11 L14 L30 | L1 L4 L8 A2 L9 L38 | L1 L9 L38 | L9 L30 L38 makes body 5 in component "Cheast Unit"
extrude "Extrude2''" cut sketch "Sketch1 (3)" along normal blind 57 contours L3 L7 L11 L12 L19 | L1 L3 L9 L12 L13 L14 L19 L30 L38 L46 | L1 L3 L46 | L7 L11 L19 L30 | L7 L9 L11 L14 L30 | L11 L12 L19 | L11 L12 L13 L14 L19 L30 | L11 L14 L30 | L1 L9 L38 bodies 5 in component "Cheast Unit"
extrude "Extrude3''" add sketch "Sketch1 (3)" against normal blind 8 from surface at -0.1 separate body contours A0 L0 L3 L6 L7 L19 | L3 L19 L46 | L0 L1 L3 L4 A1 L46 | L6 L7 L8 A3 L9 L30 | L7 L19 L30 | L3 L7 L11 L12 L19 | L1 L3 L9 L12 L13 L14 L19 L30 L38 L46 | L1 L3 L46 | L7 L11 L19 L30 | L7 L9 L11 L14 L30 | L1 L38 L46 | L1 L4 L8 A2 L9 L38 | L1 L9 L38 | L9 L30 L38 makes body 6 in component "Cheast Unit"
sketch "Sketch2 (3)" plane through (0, 0, -39.924) normal (0, 0, -1) x (-1, 0, 0) in component "Cheast Unit"
  line L0 (-153.5599, 0) -> (-73.5599, 0)
  line L1 (-73.5599, 0) -> (-73.5599, 60)
  line L2 (-73.5599, 60) -> (-153.5599, 60)
  line L3 (-153.5599, 60) -> (-153.5599, 0)
  line L4 (-113.5599, 0) -> (-113.5599, -8) construction
  line L5 (-136.0599, -5) -> (-91.0599, -5)
  line L6 (-91.0599, -5) -> (-91.0599, 5)
  line L7 (-91.0599, 5) -> (-136.0599, 5)
  line L8 (-136.0599, 5) -> (-136.0599, -5)
  line L9 (-136.0599, -5) -> (-91.0599, 5) construction
  line L10 (-91.0599, -5) -> (-136.0599, 5) construction
  line L11 (-91.2599, 4.8) -> (-135.8599, 4.8)
  line L12 (-135.8599, 4.8) -> (-135.8599, -4.8)
  line L13 (-135.8599, -4.8) -> (-91.2599, -4.8)
  line L14 (-91.2599, -4.8) -> (-91.2599, 4.8)
  line L15 (-73.5599, 1.4) -> (-70.9599, 1.4) construction
  line L16 (-68.6599, 4.9) -> (-73.4599, 4.9)
  line L17 (-71.0599, 3.5) -> (-73.5599, 3.5) construction
  line L18 (-70.9599, 3.6) -> (-73.5599, 3.6) construction
  line L19 (-73.4599, -4.9) -> (-68.6599, -4.9)
  line L20 (-68.5599, 5) -> (-73.5599, 5)
  line L21 (-73.5599, 0) -> (-68.5599, 0) construction
  line L22 (-73.5599, 0) -> (-73.5599, 1.5) construction
  line L23 (-70.9599, 1.4) -> (-70.9599, 3.6) construction
  line L24 (-73.5599, -3.5) -> (-73.5599, -1.5)
  line L25 (-73.5599, -1.4) -> (-70.9599, -1.4)
  line L26 (-73.4599, 4.9) -> (-73.4599, -4.9)
  line L27 (-68.5599, -5) -> (-68.5599, 5)
  line L28 (-73.5599, 1.5) -> (-71.0599, 1.5) construction
  line L29 (-73.5599, -5) -> (-68.5599, -5)
  line L30 (-73.5599, -5) -> (-68.5599, 5) construction
  line L31 (-73.5599, -1.5) -> (-71.0599, -1.5)
  line L32 (-71.0599, -3.5) -> (-73.5599, -3.5)
  line L33 (-71.0599, 1.5) -> (-71.0599, 3.5) construction
  line L34 (-68.5599, -5) -> (-73.5599, 5) construction
  line L35 (-71.0599, -1.5) -> (-71.0599, -3.5)
  line L36 (-73.5599, 3.5) -> (-73.5599, 1.5) construction
  line L37 (-70.9599, -3.6) -> (-73.5599, -3.6)
  line L38 (-68.6599, -4.9) -> (-68.6599, 4.9)
  line L39 (-73.5599, 5) -> (-73.5599, -5)
  line L40 (-70.9599, -1.4) -> (-70.9599, -3.6)
  line L41 (-73.5599, 0) -> (-71.0599, 0) construction
  line L42 (-153.5599, 0) -> (-156.0599, 0) construction
  line L43 (-153.5599, 0) -> (-158.5599, 0) construction
  line L44 (-153.5599, -1.5) -> (-156.0599, -1.5)
  line L45 (-153.5599, -5) -> (-158.5599, 5) construction
  line L46 (-153.5599, 0) -> (-153.5599, 1.5) construction
  line L47 (-153.5599, -5) -> (-158.5599, -5)
  line L48 (-153.5599, -1.4) -> (-156.1599, -1.4)
  line L49 (-156.0599, -1.5) -> (-156.0599, -3.5)
  line L50 (-153.5599, 5) -> (-153.5599, -5)
  line L51 (-153.6599, -4.9) -> (-158.4599, -4.9)
  line L52 (-156.1599, -3.6) -> (-153.5599, -3.6)
  line L53 (-153.5599, -3.5) -> (-153.5599, -1.5)
  line L54 (-153.6599, 4.9) -> (-153.6599, -4.9)
  line L55 (-158.4599, -4.9) -> (-158.4599, 4.9)
  line L56 (-156.1599, -1.4) -> (-156.1599, -3.6)
  line L57 (-158.5599, -5) -> (-158.5599, 5)
  line L58 (-153.5599, 1.4) -> (-156.1599, 1.4) construction
  line L59 (-156.1599, 3.6) -> (-153.5599, 3.6) construction
  line L60 (-156.0599, -3.5) -> (-153.5599, -3.5)
  line L61 (-158.5599, -5) -> (-153.5599, 5) construction
  line L62 (-158.4599, 4.9) -> (-153.6599, 4.9)
  line L63 (-153.5599, 3.5) -> (-153.5599, 1.5) construction
  line L64 (-156.0599, 3.5) -> (-153.5599, 3.5) construction
  line L65 (-156.0599, 1.5) -> (-156.0599, 3.5) construction
  line L66 (-156.1599, 1.4) -> (-156.1599, 3.6) construction
  line L67 (-153.5599, 1.5) -> (-156.0599, 1.5) construction
  line L68 (-158.5599, 5) -> (-153.5599, 5)
  point P0 (-113.5599, 0)
  point P1 (-71.0599, 0)
  point P2 (-156.0599, 0)
  point P3 (-153.5599, 0)
  dimension "d74_1" = 45
  dimension "d75_1" = 10
  dimension "d77_1" = -0.2
  dimension "d88_1" = -0.1
  dimension "d89_1" = 5
  dimension "d90_1" = 1.5
  dimension "d91_1" = 2.5
  dimension "d92_1" = 2
  dimension "d93_1" = 0.1
  dimension "d94_1" = 0.1
  dimension "d95_1" = 0.1
  dimension "d96_1" = 2.5
  constraint midpoint L0 P0
  constraint perpendicular L0 L4
  constraint horizontal L5
  constraint perpendicular L5 L6
  constraint parallel L5 L7
  constraint parallel L6 L8
  constraint coincident L9 P0
  constraint coincident L10 P0
  constraint coincident P0 L4.start
  constraint perpendicular L27 L29
  constraint parallel L20 L29
  constraint parallel L27 L39
  constraint coincident P1 L30
  constraint coincident P1 L34
  constraint midpoint P1 L21
  constraint perpendicular L21 L22
  constraint symmetric L22.end L24.end L21
  constraint symmetric L31.end L28.end L21
  constraint symmetric L17.start L32.start L21
  constraint symmetric L24.start L17.end L21
  constraint symmetric L25.end L15.end L21
  constraint symmetric L37.start L18.start L21
  constraint symmetric L25.start L15.start L21
  constraint symmetric L37.end L18.end L21
  constraint coincident L0.end L1.start
  constraint perpendicular L1 L41
  constraint symmetric L0.end L4 P3
  constraint symmetric L4 L17.start L64.start
  constraint symmetric L4 P1 P2
  constraint symmetric L4 L22.end L46.end
  constraint symmetric L4 L32.start L49.end
  constraint symmetric L4 L25.end L48.end
  constraint symmetric L4 L37.end L52.end
  constraint symmetric L4 L25.start L48.start
  constraint symmetric L4 L24.start L53.start
  constraint symmetric L4 L31.end L44.end
  constraint symmetric L4 L24.end L44.start
  constraint symmetric L4 L37.start L52.start
  constraint symmetric L4 L28.end L65.start
  constraint symmetric L4 L20.start L45.end
  constraint symmetric L4 L0.end P3
  constraint symmetric L4 L29.start L45.start
  constraint symmetric L4 L21.end L43.end
  constraint symmetric L4 L27.start L47.end
  constraint symmetric L4 L20.end L50.start
  constraint symmetric L4 L15.end L58.end
  constraint symmetric L4 L18.start L59.start
  constraint symmetric L4 L17.end L63.start
  constraint symmetric L4 L15.start L58.start
  constraint symmetric L4 L18.end L59.end
  constraint symmetric L4 L16.start L55.end
  constraint symmetric L4 L19.end L51.end
  constraint symmetric L4 L19.start L51.start
  constraint symmetric L4 L16.end L54.start
  measures "d74_1" distance of L6.end L7.end
  measures "d75_1" distance of L5.end L6.end
  measures "d89_1" distance of L0.end L21.end
  measures "d90_1" distance of L22.end L0.end
  measures "d91_1" distance of L22.end L28.end
  measures "d92_1" distance of L22.end L17.end
  measures "d93_1" distance of L15 L28
  measures "d94_1" distance of L23 L33
  measures "d95_1" distance of L17 L18
  measures "d96_1" distance of L0.end P1
extrude "Extrude4''" add sketch "Sketch2 (3)" against normal blind 2.5 contours L0 L12 L13 L14 bodies 5 in component "Cheast Unit"
extrude "Extrude5''" cut sketch "Sketch2 (3)" against normal blind 2.5 contours L0 L5 L6 L8 L12 L13 L14 | L0 L12 L13 L14 bodies 6 in component "Cheast Unit"
extrude "Extrude6''" add sketch "Sketch2 (3)" against normal blind 90 contours L3 L47 L48 L50 L51 L52 L54 L55 L57 L62 L68 | L48 L51 L52 L54 L55 L56 L62 | L1 L16 L19 L20 L25 L26 L27 L29 L37 L38 L39 | L16 L19 L25 L26 L37 L38 L40 bodies 5 in component "Cheast Unit"
extrude "Extrude7'" cut sketch "Sketch2 (3)" against normal blind 90 contours L3 L47 L48 L50 L51 L52 L54 L55 L57 L62 L68 | L44 L48 L50 L54 | L44 L48 L49 L52 L54 L56 L60 | L48 L51 L52 L54 L55 L56 L62 | L50 L52 L54 L60 | L1 L16 L19 L20 L25 L26 L27 L29 L37 L38 L39 | L25 L26 L31 L39 | L16 L19 L25 L26 L37 L38 L40 | L25 L26 L31 L32 L35 L37 L40 | L26 L32 L37 L39 bodies 6 in component "Cheast Unit"
extrude "Extrude8'" cut sketch "Sketch1 (3)" along normal mid plane 130 contours A0 L0 L3 L6 L7 L19 | L3 L19 L46 | L0 L1 L3 L4 A1 L46 | L6 L7 L8 A3 L9 L30 | L7 L19 L30 | L3 L7 L11 L12 L19 | L1 L3 L9 L12 L13 L14 L19 L30 L38 L46 | L1 L3 L46 | L7 L11 L19 L30 | L7 L9 L11 L14 L30 | L11 L12 L19 | L11 L12 L13 L14 L19 L30 | L1 L38 L46 | L11 L14 L30 | L1 L4 L8 A2 L9 L38 | L1 L9 L38 | L9 L30 L38 keep common part bodies 5 in component "Cheast Unit"
sketch "Sketch3 (2)" plane through (158.5599, 0, 0) normal (1, 0, 0) x (0, 0, -1) in component "Cheast Unit"
  line L0 (34.924, -5) -> (34.924, 60)
  line L1 (34.924, 60) -> (-45.076, 60)
  line L2 (-45.076, 60) -> (-45.076, -5)
  line L3 (-45.076, -5) -> (34.924, -5)
  line L4 (34.924, 27.5) -> (-45.076, 27.5) construction
  line L5 (34.924, 60) -> (-5.076, 27.5) construction
  circle A0 centre (14.924, 43.75) radius 5
  line L6 (-5.076, 27.5) -> (-45.076, 60) construction
  line L7 (-19.076, 46.75) -> (-31.076, 46.75)
  line L8 (-31.076, 46.75) -> (-31.076, 40.75)
  line L9 (-31.076, 40.75) -> (-19.076, 40.75)
  line L10 (-19.076, 40.75) -> (-19.076, 46.75)
  line L11 (-19.076, 46.75) -> (-31.076, 40.75) construction
  line L12 (-31.076, 46.75) -> (-19.076, 40.75) construction
  point P0 (-25.076, 43.75)
  dimension "d110_1" = 10
  dimension "d138" = 12
  dimension "d139" = 6
  constraint midpoint L0 L4.start
  constraint midpoint L2 L4.end
  constraint coincident L0.end L1.start
  constraint midpoint L4 L5.end
  constraint midpoint L5 A0.centre
  constraint coincident L1.end L2.start
  constraint horizontal L7
  constraint perpendicular L7 L8
  constraint parallel L7 L9
  constraint parallel L8 L10
  constraint coincident L11 P0
  constraint coincident L12 P0
  constraint midpoint L6 P0
  measures "d110_1" diameter of A0
  measures "d138" distance of L8.end L9.end
  measures "d139" distance of L7.end L8.end
extrude "Extrude9''" cut sketch "Sketch3 (2)" against normal blind 5 contours A0 | L7 L8 L9 L10 bodies 5 in component "Cheast Unit"
extrude "Extrude12" add sketch "Sketch1 (3)" along normal blind 5 from surface at 55 contours A0 L0 L6 L20 L21 L22 | L0 L4 A1 L45 L47 L48 | L6 L8 A3 L29 L31 L32 | L4 L8 A2 L37 L39 L40 bodies 5 in component "Cheast Unit"
chamfer "Chamfer1" distance 5 angle 45 12 edges at (68.5599, 55, -14.924) (70.0244, 55, -38.4595) (93.5599, 55, -39.924) (68.5599, 55, 25.076) (70.0244, 55, 48.6116) (93.5599, 55, 50.076) (133.5599, 55, -39.924) (157.0954, 55, -38.4595) (158.5599, 55, -14.924) (158.5599, 55, 25.076) (157.0954, 55, 48.6116) (133.5599, 55, 50.076) tangent chain off on bodies 5 in component "Cheast Unit"
sketch "Sketch3 (3)" plane through (-30, 0, 0) normal (-1, 0, 0) x (0, 0, 1) in component "Wrist unit"
  line L0 (-10, 5) -> (-10, -25)
  line L1 (-10, -25) -> (10, -25)
  line L2 (10, -25) -> (10, 5)
  line L3 (10, 5) -> (-10, 5)
  line L4 (-10, -10) -> (10, -10)
  line L5 (10, -10) -> (10, -20)
  line L6 (10, -20) -> (-10, -20)
  line L7 (-10, -20) -> (-10, -10)
  constraint horizontal L4
  constraint vertical L5
  constraint horizontal L6
  constraint vertical L7
  constraint coincident L2 L5.end
  constraint midpoint L0 L4.start
extrude "Extrude12'" cut sketch "Sketch3 (3)" against normal blind 10 contours L0 L2 L4 L5 L6 L7 bodies 1 in component "Wrist unit"
component "Gas Unit" placed x (1, 0, 0) y (0, -1, 0) z (0, 0, -1) at (150, 18.0941, 5.99)
component "Wrist unit" placed x (1, 0, 0) y (0, 1, 0) z (0, 0, 1) at (0, 0, 0)
component "Cheast Unit" placed x (1, 0, 0) y (0, -1, 0) z (0, 0, -1) at (0, 30, 10.1521)
